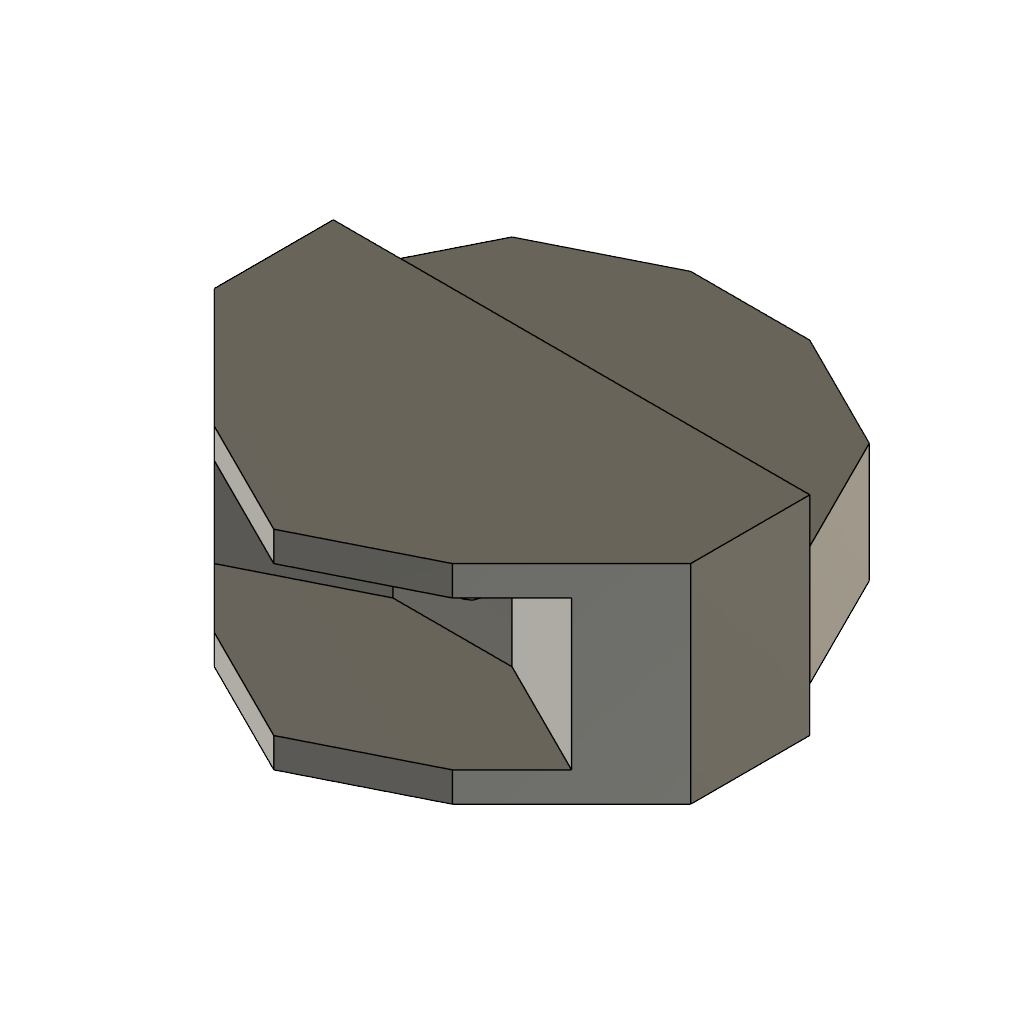
pieza_2 (Autodesk Fusion 360 design; units mm, degrees)
part number: 2026-11-08-01-03-03-747
Autodesk Fusion 360 part; units mm, degrees
sketch "Boceto1" plane through (0, 0, 0) normal (0, 0, 1) x (1, 0, 0)
  line L0 (40, 0) -> (40, 10)
  line L1 (40, 10) -> (35, 20)
  line L2 (35, 20) -> (25, 25)
  line L3 (25, 25) -> (15, 25)
  line L4 (15, 25) -> (5, 20)
  line L5 (5, 20) -> (0, 10)
  line L6 (0, 10) -> (0, 0)
  line L7 (40, 0) -> (30, -10)
  line L8 (0, 0) -> (10, -10)
  line L9 (30, -10) -> (20, -15)
  line L10 (20, -15) -> (10, -10)
  line L11 (25, 25) -> (15, 25) construction
  line L12 (0, 10) -> (40, 10)
  point P0 (18.6603, 5)
  constraint coincident L6.end L8.start
  constraint parallel L3 L11
sketch "Boceto2" plane through (0, 0, 0) normal (0, 0, 1) x (1, 0, 0)
  line L0 (0, 10, 2.5) -> (40, 10, 2.5)
  line L1 (40, 10, 2.5) -> (35, 20, 2.5)
  line L2 (35, 20, 2.5) -> (25, 25, 2.5)
  line L3 (25, 25, 2.5) -> (15, 25, 2.5)
  line L4 (15, 25, 2.5) -> (5, 20, 2.5)
  line L5 (5, 20, 2.5) -> (0, 10, 2.5)
extrude "Extruir1" add sketch "Boceto1" along normal blind 2.5 contours L0 L6 L7 L8 L9 L10 L12 makes body 1
copy_body "CopiarPegarCuerpos1" bodies 1 makes body 2
move_body "Desplazar1" bodies 2 to x (1, 0, 0) y (0, 1, 0) z (0, 0, 1) at (0, 0, 12.5)
move_body "Desplazar2" bodies 2 to x (1, 0, 0) y (0, 1, 0) z (0, 0, 1) at (0, 0, 2.5)
sketch "Boceto3" plane through (0, 0, 0) normal (0, 0, 1) x (1, 0, 0)
extrude "Extruir2" add sketch "Boceto2" along normal blind 10 separate body contours L0 L1 L2 L3 L4 L5 in plane through (0, 0, 2.5) normal (0, 0, 1) makes body 3
sketch "Boceto4" plane through (0, 0, 2.5) normal (0, 0, 1) x (-1, 0, 0)
  line L0 (0, 0) -> (-10, 10)
  line L1 (-10, 10) -> (-20, 15)
  line L2 (-20, 15) -> (-30, 10)
  line L3 (-30, 10) -> (-40, 0)
  line L4 (-40, -10) -> (0, -10)
  line L5 (-15, 15) -> (-15, 15.5044)
  line L6 (-15, 0) -> (-25, 0)
  line L7 (-25, 0) -> (-35, 5)
  line L8 (-15, 0) -> (-5, 5)
  line L9 (0, -10) -> (-40, -10)
  line L10 (-35, 5) -> (-40, 0)
  line L11 (-15, 0) -> (-25, 0)
  line L12 (0, -10) -> (-40, -10)
  line L13 (-25, 0) -> (-15, 0)
  line L14 (0, -10) -> (-40, -10)
  line L15 (0, -10) -> (0, 0)
  line L16 (0, -10) -> (0, 0)
  line L17 (0, 0) -> (-5, 5)
  line L18 (-35, 5) -> (-40, 0)
  line L19 (-40, -10) -> (-40, 0)
  constraint perpendicular L4 L5
  constraint midpoint L3 L7.end
  constraint midpoint L0 L8.end
  constraint coincident L4.end L9.start
  constraint coincident L4.start L9.end
  constraint coincident L3.end L10.end
  constraint coincident L0.start L15.end
move_body "Desplazar3" bodies 3 to x (1, 0, 0) y (0, 1, 0) z (0, 0, 1) at (0, 0, 1.25)
extrude "Extruir4" add sketch "Boceto4" along normal blind 12.5 contours L0 L3 L4 L6 L7 L8 L9 L10 L11 L12 L13 L14 L15 L16 L17 L18 L19 bodies 1 2 3
extrude "Extruir3" add sketch "Boceto4" along normal blind 10 contours L0 L3 L4 L6 L7 L8 L9 L10 L11 L12 L13 L14 L15 L16 L17 L18 L19 bodies 1
hole "Agujero1" at (20, 0, 8.75) direction (0, 1, 0) diameter 7 depth 8 tip angle 180 bodies 1
hole "Agujero2" at (20, 25, 8.75) direction (0, -1, 0) diameter 7 depth 8 tip angle 180 bodies 1
hole "Agujero3" at (10, 22.5, 8.75) direction (0.447214, -0.894427, 0) diameter 7 depth 8 tip angle 180 bodies 1
hole "Agujero4" at (30, 22.5, 8.75) direction (-0.447214, -0.894427, 0) diameter 7 depth 8 tip angle 180 bodies 1
